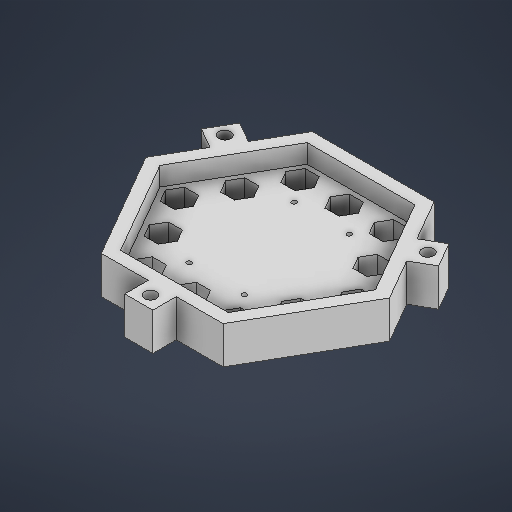
# Autodesk Inventor part: AVBay
Saved by Autodesk Inventor 2026.3 (Build 303398000, 398)
## iProperties
Created: 2026-06-26
Part Number: AVBay
Material: Generic
Document SubType Name: Modeling
Designer: joaqu
Density: 1 g/cm^3
Appearance: Default
Author: joaqu
Autodesk Inventor part; units mm, degrees
ref_plane "YZ Plane" through (0, 0, 0) normal (1, 0, 0) x (0, 1, 0)
ref_plane "XZ Plane" through (0, 0, 0) normal (0, 1, 0) x (-1, 0, 0)
ref_plane "XY Plane" through (0, 0, 0) normal (0, 0, 1) x (1, 0, 0)
sketch "Sketch1" plane through (0, 0, 0) normal (0, 1, 0) x (-1, 0, 0)
  line L0 (-115, 0) -> (-57.5, 99.5929)
  line L1 (-57.5, 99.5929) -> (57.5, 99.5929)
  line L2 (57.5, 99.5929) -> (115, 0)
  line L3 (115, 0) -> (57.5, -99.5929)
  line L4 (57.5, -99.5929) -> (-57.5, -99.5929)
  line L5 (-57.5, -99.5929) -> (-115, 0)
  line L6 (-130, 0) -> (-65, 112.5833)
  line L7 (-65, 112.5833) -> (65, 112.5833)
  line L8 (65, 112.5833) -> (130, 0)
  line L9 (130, 0) -> (65, -112.5833)
  line L10 (65, -112.5833) -> (-65, -112.5833)
  line L11 (-65, -112.5833) -> (-130, 0)
  point P0 (0, 0)
  point P1 (0, 0)
  point P2 (0, 0)
  dimension "d0" = 115
  dimension "d2" = 130
  constraints: 24 end point, 2 coincident, 26 other
  measures "d0" distance of L3.end L4.end
  measures "d2" distance of L9.end L10.end
extrude "Extrusion1" add sketch "Sketch1" along normal blind 40
sketch "Sketch3" plane through (-65, 0, 112.5833) normal (0, 0, 1) x (1, 0, 0)
  line L0 (130, 0) -> (0, 0) projected
  line L1 (130, 40) -> (0, 40) projected
  line L2 (50, 0) -> (80, 0)
  line L3 (80, 0) -> (80, 40)
  line L4 (80, 40) -> (50, 40)
  line L5 (50, 40) -> (50, 0)
  point P0 (65, 0)
  point P1 (65, 0)
  point P2 (65, 0)
  dimension "d5" = 15
  dimension "d6" = 15
  constraints: 8 end point, 2 midpoint, 2 parallel, 2 point on line, 1 horizontal, 1 perpendicular
  measures "d5" distance from line of L5 point (65, 0)
  measures "d6" distance from line of L3 point (65, 0)
extrude "Extrusion2" add sketch "Sketch3" along normal blind 25
pattern_circular "Circular Pattern1" count 3 over 360 about axis through (0, -10, 0) along (0, 1, 0) of "Extrusion2"
sketch "Sketch7" plane through (0, 40, 0) normal (0, 1, 0) x (1, 0, 0)
  line L0 (115.8253, 49.5513) -> (100.8253, 75.532) projected
  circle A0 centre (108.3253, 62.5417) radius 6.375
  point P0 (0, 0)
  dimension "d24" = 12.75
  constraints: 1 centre point, 1 midpoint
  measures "d24" diameter of A0
extrude "Extrusion4" cut sketch "Sketch7" against normal blind 79.85
pattern_circular "Circular Pattern2" count 3 over 360 about axis through (0, -10, 0) along (0, 1, 0) of "Extrusion4"
sketch "Sketch8" plane through (0, 0, 0) normal (0, 1, 0) x (-1, 0, 0)
  line L0 (-115, 0) -> (-57.5, 99.5929)
  line L1 (-57.5, 99.5929) -> (57.5, 99.5929)
  line L2 (57.5, 99.5929) -> (115, 0)
  line L3 (115, 0) -> (57.5, -99.5929)
  line L4 (57.5, -99.5929) -> (-57.5, -99.5929)
  line L5 (-57.5, -99.5929) -> (-115, 0)
  line L6 (-130, 0) -> (-65, 112.5833)
  line L7 (-65, 112.5833) -> (65, 112.5833)
  line L8 (65, 112.5833) -> (130, 0)
  line L9 (130, 0) -> (65, -112.5833)
  line L10 (65, -112.5833) -> (-65, -112.5833)
  line L11 (-65, -112.5833) -> (-130, 0)
  point P0 (0, 0)
  point P1 (0, 0)
  point P2 (0, 0)
  point P3 (0, 0)
  dimension "d31" = 115
  dimension "d32" = 130
  dimension "d33" = 0
  dimension "d34" = 0
  constraints: 24 end point, 2 coincident, 26 other
  measures "d31" distance of L3.end L4.end
  measures "d32" distance of L9.end L10.end
  measures "d33" distance of point (0, 0) point (0, 0)
  measures "d34" distance of point (0, 0) point (0, 0)
extrude "Extrusion5" add sketch "Sketch8" along normal blind 20 contours L0 L1 L2 L3 L4 L5
sketch "Sketch9" plane through (0, 20, 0) normal (0, 1, 0) x (1, 0, 0)
  line L0 (-119.799, 2.7708) -> (-62.2991, 102.3636)
  line L1 (-57.5, -99.5929) -> (-115, 0) projected
  line L2 (-57.5, 99.5929) -> (57.5, 99.5929) projected
  line L3 (0, 99.5929) -> (0, -99.5929)
  line L4 (57.5, -99.5929) -> (-57.5, -99.5929) projected
  line L5 (-115, 0) -> (115, 0)
  line L6 (-79.2265, 0) -> (-86.7265, -12.9904)
  line L7 (-86.7265, -12.9904) -> (-101.7265, -12.9904)
  line L8 (-101.7265, -12.9904) -> (-109.2265, 0)
  line L9 (-109.2265, 0) -> (-101.7265, 12.9904)
  line L10 (-101.7265, 12.9904) -> (-86.7265, 12.9904)
  line L11 (-86.7265, 12.9904) -> (-79.2265, 0)
  line L12 (-115, 0) -> (-57.5, 99.5929) projected
  line L13 (57.5, 99.5929) -> (115, 0) projected
  point P0 (0, 0)
  point P1 (0, 0)
  point P2 (0, 0)
  point P3 (0, 0)
  point P4 (0, 0)
  point P5 (0, 0)
  point P6 (-94.2265, 0)
  point P7 (-94.2265, 12.9904)
  point P8 (21.1742, -18.2327)
  point P9 (21.1742, -18.2327)
  point P10 (21.1742, -18.2327)
  point P11 (21.1742, -18.2327)
  point P12 (21.1742, -18.2327)
  point P13 (21.1742, -18.2327)
  dimension "d66" = 15
  dimension "d68" = 0
  dimension "d89" = 5
  constraints: 18 end point, 10 coincident, 4 midpoint, 1 horizontal, 13 other
  measures "d66" distance of L9.end L10.end
  measures "d68" distance from line of L5 L8.end
  measures "d89" distance between parallel lines of L9 L12
extrude "Extrusion7" cut sketch "Sketch9" against normal blind 20 contours L9 L10 L11 L5 | L5 L6 L7 L8
pattern_circular "Circular Pattern3" count 6 over 360 about axis through (0, -10, 0) along (0, 1, 0) of "Extrusion7"
sketch "Sketch10" plane through (0, 20, 0) normal (0, 1, 0) x (1, 0, 0)
  line L0 (-78.1699, 27.8109) -> (-85.6699, 40.8013)
  line L1 (-85.6699, 40.8013) -> (-78.1699, 53.7917)
  line L2 (-78.1699, 53.7917) -> (-63.1699, 53.7917)
  line L3 (-63.1699, 53.7917) -> (-55.6699, 40.8013)
  line L4 (-55.6699, 40.8013) -> (-63.1699, 27.8109)
  line L5 (-63.1699, 27.8109) -> (-78.1699, 27.8109)
  line L6 (-55.1341, 99.5929) -> (57.5, 99.5929)
  line L7 (-57.5, -99.5929) -> (-113.817, -2.0489)
  line L8 (-44.7542, 99.5929) -> (57.5, 99.5929)
  line L9 (-62.1132, 81.6025) -> (-54.6132, 68.6122) projected
  line L10 (-54.6132, 68.6122) -> (-86.7265, 12.9904)
  point P0 (-70.6699, 40.8013)
  point P1 (-81.9199, 47.2965)
  point P2 (-70.6699, 40.8013)
  dimension "d94" = 15
  constraints: 20 end point, 2 midpoint, 1 coincident, 13 other
  measures "d94" distance of L1.end L2.end
extrude "Extrusion8" cut sketch "Sketch10" against normal blind 20
pattern_circular "Circular Pattern4" count 6 over 360 about axis through (0, -10, 0) along (0, 1, 0) of "Extrusion8"
sketch "Sketch11" plane through (0, 20, 0) normal (0, 1, 0) x (1, 0, 0)
  line L0 (0, 0) -> (0, 63.5) construction
  line L1 (0, 0) -> (0, 63.5) construction
  line L2 (0, 63.5) -> (36.83, 63.5) construction
  line L3 (36.83, 63.5) -> (36.83, -63.5) construction
  line L4 (36.83, -63.5) -> (-36.83, -63.5) construction
  line L5 (-36.83, -63.5) -> (-36.83, 63.5) construction
  line L6 (-36.83, 63.5) -> (0, 63.5) construction
  line L7 (-29.5936, 63.5) -> (-29.5936, 57.5)
  line L8 (-36.83, 57.5) -> (-29.33, 57.5)
  circle A0 centre (-29.33, 57.5) radius 2.5
  line L9 (-29.33, 57.5) -> (29.67, 57.5)
  circle A1 centre (29.67, 57.5) radius 2.5
  line L10 (29.67, -54.5) -> (-29.33, -54.5)
  circle A2 centre (-29.33, -54.5) radius 2.5
  circle A3 centre (29.67, -54.5) radius 2.5
  dimension "d115" = 36.83
  dimension "d116" = 127
  dimension "d117" = 73.66
  dimension "d142" = 6
  dimension "d143" = 7.5
  dimension "d144" = 5
  dimension "d145" = 59
  dimension "d146" = 5
  dimension "d147" = 112
  dimension "d148" = 5
  dimension "d149" = 5
  constraints: 22 end point, 6 perpendicular, 4 centre point, 4 coincident, 4 point on line, 2 collinear, 1 vertical
  measures "d115" distance of L0.end L2.end
  measures "d116" distance of L2.end L3.end
  measures "d117" distance of L3.end L4.end
  measures "d142" distance of L7.start L7.end
  measures "d143" distance of L8.start L8.end
  measures "d144" diameter of A0
  measures "d145" distance of L9.start L9.end
  measures "d146" diameter of A1
  measures "d147" distance of A1.centre L10.start
  measures "d148" diameter of A2
  measures "d149" diameter of A3
extrude "Extrusion10" cut sketch "Sketch11" against normal up to surface (20 mm away)
body "Solid1"
